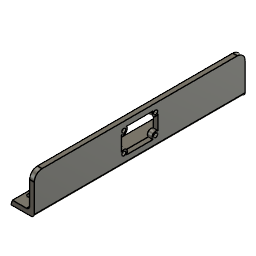
ToF_mount_side (Autodesk Fusion 360 archive; units mm, degrees)
design "ToF_mount_side"
part number: 2026-07-28-08-37-40-421
Autodesk Fusion 360 part; units mm, degrees
sketch "Sketch1" plane through (0, 0, 0) normal (0, 0, 1) x (1, 0, 0)
  line L0 (0, 0) -> (15, 0)
  line L1 (15, 0) -> (15, 25)
  line L2 (15, 25) -> (0, 25)
  line L3 (0, 25) -> (0, 0)
  dimension "d5" = 15
  dimension "d6" = 25
  constraint horizontal L0
  constraint vertical L1
  constraint horizontal L2
  constraint vertical L3
  constraint coincident L0.start L3.end
  measures "d5" distance of L1.end L2.end
  measures "d6" distance of L0.end L1.end
extrude "Extrude2" add sketch "Sketch1" along normal mid plane 135
sketch "Sketch2" plane through (0, 0, 67.5) normal (0, 0, 1) x (1, 0, 0)
  line L0 (0, 25) -> (0, 0)
  line L1 (0, 0) -> (15, 0)
  line L2 (15, 0) -> (15, 25)
  line L3 (15, 25) -> (0, 25)
  line L4 (0, 25) -> (12, 25)
  line L5 (12, 25) -> (12, 3)
  line L6 (12, 3) -> (0, 3)
  line L7 (0, 3) -> (0, 25)
  line L8 (15, 0) -> (15, 25)
  line L9 (0, 0) -> (15, 0)
  dimension "d9" = 3
  dimension "d10" = 3
  constraint horizontal L4
  constraint vertical L5
  constraint horizontal L6
  constraint vertical L7
  constraint coincident L0.start L3.end
  measures "d9" distance of L5 L8
  measures "d10" distance of L6 L9
extrude "Extrude3" cut sketch "Sketch2" against normal blind 135 contours L0 L3 L4 L5 L6 L7
fillet "Fillet1" radius 2 1 edges at (12, 3, 0)
fillet "Fillet2" radius 2 1 edges at (15, 0, 0)
fillet "Fillet3" radius 5 2 edges at (13.5, 25, 67.5) (13.5, 25, -67.5)
sketch "Sketch3" plane through (0, 3, 0) normal (0, 1, 0) x (-1, 0, 0)
  line L0 (-10, 67.5) -> (-10, -67.5)
  line L1 (-10, -67.5) -> (0, -67.5)
  line L2 (0, -67.5) -> (0, 67.5)
  line L3 (0, 67.5) -> (-10, 67.5)
  line L4 (0, 0) -> (17.7157, 0) construction
  circle A0 centre (-4, -59.25) radius 1.5
  circle A1 centre (-4, 59.25) radius 1.5
  dimension "d19" = 118.5
  dimension "d28" = 3
  dimension "d32" = 4
  constraint coincident L4.start origin
  constraint perpendicular L2 L4
  constraint vertical A0.centre A1.centre
  constraint symmetric L4 A0.centre A1.centre
  constraint equal A0 A1
  measures "d19" distance of A0.centre A1.centre
  measures "d28" diameter of A1
  measures "d32" distance of L2 A1.centre
extrude "Extrude4" cut sketch "Sketch3" against normal blind 3 contours A0 | A1
sketch "Sketch4" plane through (15, 0, 0) normal (1, 0, 0) x (0, 0, -1)
  arc A0 (67.5, 20) -> (62.5, 25) centre (62.5, 20) ccw
  line L0 (62.5, 25) -> (-62.5, 25)
  arc A1 (-62.5, 25) -> (-67.5, 20) centre (-62.5, 20) ccw
  line L1 (-67.5, 20) -> (-67.5, 2)
  line L2 (-67.5, 2) -> (67.5, 2)
  line L3 (67.5, 2) -> (67.5, 20)
  line L4 (0, 0) -> (0, 40) construction
  circle A2 centre (-10.16, 20) radius 1.5
  circle A3 centre (10.16, 20) radius 1.5
  line L5 (0, 0) -> (0, 25)
  circle A4 centre (-10.16, 7.3) radius 1.5
  circle A5 centre (10.16, 7.3) radius 1.5
  dimension "d22" = 3
  dimension "d24" = 20.32
  dimension "d25" = 5
  dimension "d29" = 12.7
  constraint coincident L4.start L5.start
  constraint perpendicular L0 L4
  constraint symmetric A2.centre A3.centre L5
  constraint equal A2 A3
  constraint equal A2 A4
  constraint equal A2 A5
  constraint vertical A2.centre A4.centre
  constraint horizontal A4.centre A5.centre
  constraint vertical A3.centre A5.centre
  measures "d22" diameter of A2
  measures "d24" distance of A2.centre A3.centre
  measures "d25" distance of L0 A2.centre
  measures "d29" distance of A2.centre A4.centre
sketch "Sketch7" plane through (0, 0, -67.5) normal (0, 0, -1) x (-1, 0, 0)
  line L0 (-12, 20) -> (-15, 20)
  line L1 (-15, 20) -> (-15, 2)
  arc A0 (-15, 2) -> (-13, 0) centre (-13, 2) ccw
  line L2 (-13, 0) -> (0, 0)
  line L3 (0, 0) -> (0, 3)
  line L4 (0, 3) -> (-10, 3)
  arc A1 (-12, 5) -> (-10, 3) centre (-10, 5) ccw
  line L5 (-12, 5) -> (-12, 20)
  line L6 (0, 0) -> (0, 3)
  line L7 (0, 3) -> (-1, 3)
  line L8 (-1, 3) -> (0, 0)
  dimension "d33" = 1
  constraint coincident L2.end L3.start
  constraint coincident L3.end L4.start
  constraint coincident L4 L7.end
  measures "d33" distance of L3.end L7.end
extrude "Extrude7" cut sketch "Sketch7" against normal blind 135 contours L3 L4 L6 L7 L8
sketch "Sketch9" plane through (15, 0, 0) normal (1, 0, 0) x (0, 0, -1)
  arc A0 (67.5, 20) -> (62.5, 25) centre (62.5, 20) ccw
  line L0 (62.5, 25) -> (-62.5, 25)
  arc A1 (-62.5, 25) -> (-67.5, 20) centre (-62.5, 20) ccw
  line L1 (-67.5, 20) -> (-67.5, 2)
  line L2 (-67.5, 2) -> (67.5, 2)
  line L3 (67.5, 2) -> (67.5, 20)
  circle A2 centre (-10.16, 19.85) radius 1.3
  circle A3 centre (10.16, 19.85) radius 1.3
  circle A4 centre (-10.16, 7.15) radius 1.3
  circle A5 centre (10.16, 7.15) radius 1.3
  line L4 (-45.1334, 13.5) -> (-31.1334, 13.5)
  line L5 (0, 2) -> (0, 15) construction
  dimension "d39" = 2.6
  dimension "d40" = 12.7
  dimension "d41" = 20.32
  constraint equal A2 A3
  constraint equal A2 A4
  constraint equal A2 A5
  constraint horizontal L4
  constraint horizontal A2.centre A3.centre
  constraint vertical A2.centre A4.centre
  constraint horizontal A4.centre A5.centre
  constraint vertical A3.centre A5.centre
  constraint symmetric A2.centre A4.centre L4
  constraint midpoint L2 L5.start
  constraint perpendicular L2 L5
  constraint symmetric A4.centre A5.centre L5
  measures "d39" diameter of A2
  measures "d40" distance of A2.centre A4.centre
  measures "d41" distance of A2.centre A3.centre
extrude "Extrude8" cut sketch "Sketch9" against normal blind 3 contours A2 | A3 | A4 | A5
sketch "Sketch11" plane through (15, 0, 0) normal (1, 0, 0) x (0, 0, -1)
  arc A0 (67.5, 20) -> (62.5, 25) centre (62.5, 20) ccw
  line L0 (62.5, 25) -> (-62.5, 25)
  arc A1 (-62.5, 25) -> (-67.5, 20) centre (-62.5, 20) ccw
  line L1 (-67.5, 20) -> (-67.5, 2)
  line L2 (-67.5, 2) -> (67.5, 2)
  line L3 (67.5, 2) -> (67.5, 20)
  line L4 (10.16, 22.39) -> (-10.16, 22.39)
  circle A2 centre (-10.16, 7.15) radius 1.25
  arc A3 (-11.7, 18.2096) -> (-8.5196, 21.39) centre (-10.16, 19.85) ccw
  circle A4 centre (10.16, 7.15) radius 1.25
  arc A5 (10.16, 4.61) -> (12.7, 7.15) centre (10.16, 7.15) ccw
  line L5 (-8.5196, 21.39) -> (8.5196, 21.39)
  line L6 (-10.16, 4.61) -> (10.16, 4.61)
  arc A6 (-12.7, 7.15) -> (-10.16, 4.61) centre (-10.16, 7.15) ccw
  arc A7 (-8.5196, 5.61) -> (-11.7, 8.7904) centre (-10.16, 7.15) ccw
  circle A8 centre (-10.16, 19.85) radius 1.25
  line L7 (8.5196, 5.61) -> (-8.5196, 5.61)
  arc A9 (-10.16, 22.39) -> (-12.7, 19.85) centre (-10.16, 19.85) ccw
  arc A10 (12.7, 19.85) -> (10.16, 22.39) centre (10.16, 19.85) ccw
  line L8 (-12.7, 19.85) -> (-12.7, 7.15)
  arc A11 (8.5196, 21.39) -> (11.7, 18.2096) centre (10.16, 19.85) ccw
  line L9 (11.7, 18.2096) -> (11.7, 8.7904)
  line L10 (-11.7, 8.7904) -> (-11.7, 18.2096)
  line L11 (12.7, 7.15) -> (12.7, 19.85)
  circle A12 centre (10.16, 19.85) radius 1.25
  arc A13 (11.7, 8.7904) -> (8.5196, 5.61) centre (10.16, 7.15) ccw
  point P0 (0, 13.5)
extrude "Extrude10" cut sketch "Sketch11" against normal blind 3 contours A3 L5 A7 L7 A11 L9 L10 A13
